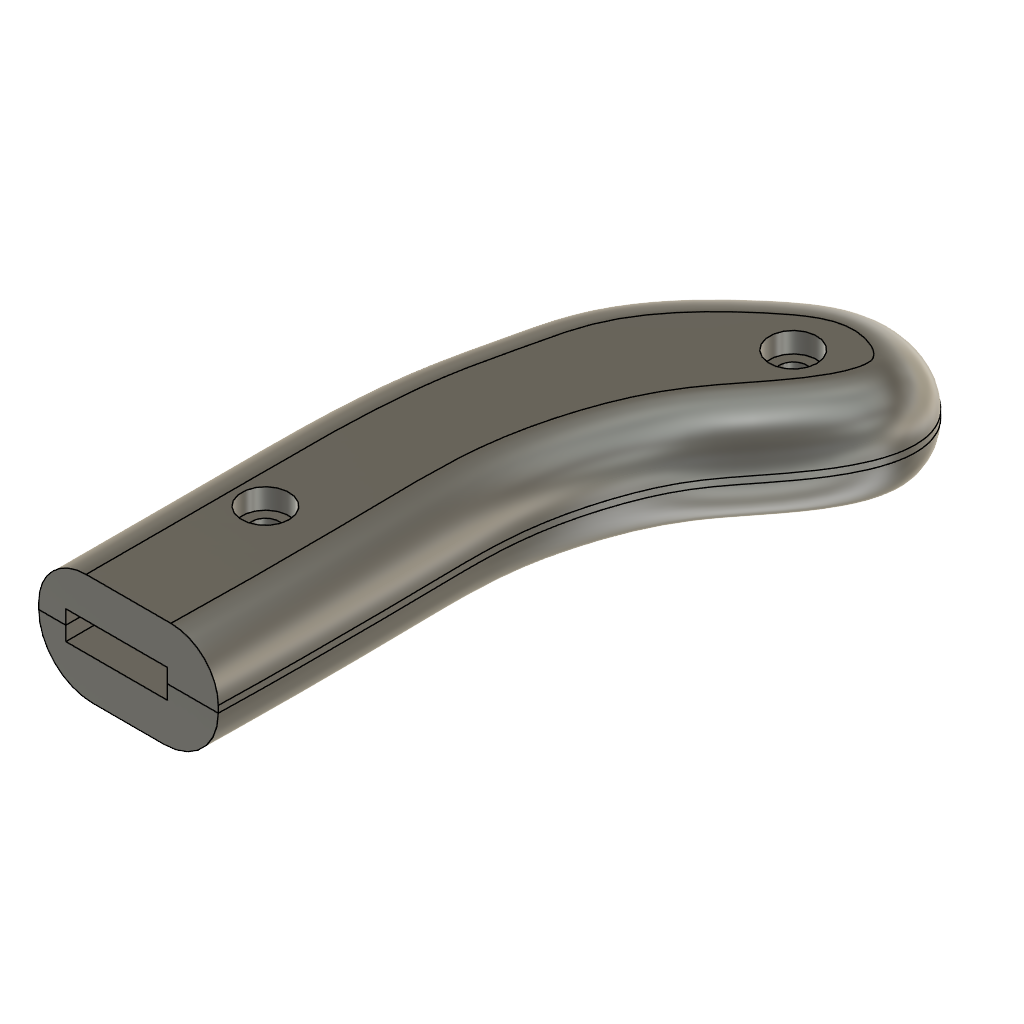
rack_handle (Autodesk Fusion 360 design; units mm, degrees)
part number: 2026-10-31-14-08-03-818
Autodesk Fusion 360 part; units mm, degrees
sketch "Sketch1" plane through (0, 0, 0) normal (0, 0, 1) x (1, 0, 0)
  line L0 (-7.5, 0) -> (7.5, 0)
  line L1 (7.5, 0) -> (7.5, 37)
  line L2 (7.5, 37) -> (-7.5, 37)
  line L3 (-7.5, 37) -> (-7.5, 0)
  arc A0 (7.5, 33) -> (3.5, 37) centre (3.5, 33) ccw
  arc A1 (-3.5, 37) -> (-7.5, 33) centre (-3.5, 33) ccw
  spline S0 degree 5 poles (-11.5, 0) (-11.5, 0.1964) (-11.4998, 0.8627) (-11.499, 2.6836) (-11.4971, 6.5461) (-11.4944, 12.661) (-11.4926, 18.7411) (-11.4942, 23.7765) (-11.4983, 27.24) (-11.5109, 30.0986) (-11.5138, 33.526) (-11.4572, 37.6506) (-11.2874, 42.3069) (-10.9623, 47.0376) (-10.4697, 51.3973) (-9.8513, 55.1652) (-9.1822, 58.3544) (-8.5348, 61.1068) (-7.9502, 63.632) (-7.4003, 66.121) (-6.7728, 68.6921) (-5.9239, 71.406) (-4.715, 74.2706) (-3.0647, 77.2483) (-0.9577, 80.2674) (1.556, 83.2437) (4.3816, 86.0885) (7.3422, 88.7451) (10.2864, 91.1577) (13.3024, 93.1642) (16.5166, 94.5809) (20.0236, 95.2277) (23.7599, 94.9782) (27.406, 93.7983) (30.5155, 91.7368) (32.6499, 88.9157) (33.4969, 85.5191) (33.0312, 81.7882) (31.5054, 77.9906) (29.3161, 74.3724) (26.9013, 71.1115) (24.6364, 68.2779) (22.7031, 65.7728) (21.0938, 63.3607) (19.715, 60.776) (18.4534, 57.7934) (17.2759, 54.3441) (16.25, 50.5096) (15.4785, 46.4111) (15.0382, 42.0502) (14.9508, 37.3279) (15.0617, 31.616) (15.1718, 24.5363) (15.219, 16.6784) (15.1847, 9.0086) (15.1016, 2.7613) (15.0348, -0.1466) (15.0063, -0.7371) (15, -0.3721) (15, 0) knots 0 0 0 0 0 0 0.018182 0.036364 0.054545 0.072727 0.090909 0.109091 0.127273 0.145455 0.163636 0.181818 0.2 0.218182 0.236364 0.254545 0.272727 0.290909 0.309091 0.327273 0.345455 0.363636 0.381818 0.4 0.418182 0.436364 0.454545 0.472727 0.490909 0.509091 0.527273 0.545455 0.563636 0.581818 0.6 0.618182 0.636364 0.654545 0.672727 0.690909 0.709091 0.727273 0.745455 0.763636 0.781818 0.8 0.818182 0.836364 0.854545 0.872727 0.890909 0.909091 0.927273 0.945455 0.963636 0.981818 1 1 1 1 1 1
  line L4 (15, -1.4596) -> (15, 1.4596)
  line L5 (15, 46.1457) -> (15, 27.8543)
  circle A2 centre (0, 22) radius 2.05
  line L6 (0, 22) -> (-7.5, 22) construction
  line L7 (0, 22) -> (7.5, 22) construction
  line L8 (-11.5, -1.8049) -> (-11.5, 1.8049)
  line L9 (-11.4851, 20.6483) -> (-11.5149, 33.3517)
  circle A3 centre (7.0828, 72.0757) radius 2
  circle A4 centre (7.0828, 72.0757) radius 2.1
  circle A5 centre (-0.8976, 46.6054) radius 2
  circle A6 centre (-0.8976, 46.6054) radius 2.1
  circle A7 centre (8.6082, 58.1337) radius 2
  circle A8 centre (8.6082, 58.1337) radius 2.1
  line L10 (0, 1.75) -> (0, 22.5)
  line L11 (1.75, 0) -> (22.5, 0)
  line L12 (-1.5998, 80.4412) -> (11.5998, 92.7436)
  line L13 (15, 0) -> (-11.5, 0)
  circle A9 centre (19, 81) radius 2.05
  point P0 (-11.5, 27)
  point P1 (-10.8099, 48.1063)
  point P2 (-8.1091, 62.9606)
  point P3 (-5.4083, 72.5258)
  point P4 (5, 86.5924)
  point P5 (20, 95)
  point P6 (26, 70)
  point P7 (19, 59)
  point P8 (15, 37)
  point P9 (32.8527, 87.3801)
  dimension "d11" = 15
  dimension "d13" = 4
  dimension "d14" = 4
  dimension "d15" = 4
  dimension "d16" = 4
  dimension "d17" = 7.5
  dimension "d18" = 7.5
  dimension "d19" = 7.5
  dimension "d20" = 7.5
  dimension "d22" = 4
  dimension "d23" = 4
  dimension "d35" = 4.1
  dimension "d36" = 15
  dimension "d54" = 4
  dimension "d55" = 4.2
  dimension "d56" = 4
  dimension "d57" = 4.2
  dimension "d58" = 4
  dimension "d59" = 4.2
  dimension "d69" = 22
  dimension "d70" = 4.1
  constraint horizontal L0
  constraint vertical L1
  constraint horizontal L2
  constraint vertical L3
  constraint coincident L1 A0.start
  constraint coincident L2 A0.end
  constraint coincident L3 A1.end
  constraint coincident L2 A1.start
  constraint tangent L2 A0
  constraint tangent L2 A1
  constraint midpoint S0.end L4
  constraint midpoint P8 L5
  constraint coincident L2 P8
  constraint coincident L0 S0.end
  constraint coincident A2.centre L6.start
  constraint coincident L3 L6.end
  constraint perpendicular L3 L6
  constraint coincident L1 L7.end
  constraint perpendicular L1 L7
  constraint equal L6 L7
  constraint midpoint S0.start L8
  constraint midpoint P0 L9
  constraint concentric A3 A4
  constraint concentric A5 A6
  constraint concentric A7 A8
  constraint coincident A2.centre L10
  constraint collinear L0 L11
  constraint parallel L8 L10
  constraint midpoint P4 L12
  constraint perpendicular L8 L13
  measures "d11" distance of L0.start L0.end
  measures "d13" distance of L2 A0.centre
  measures "d14" distance of L1 A0.centre
  measures "d15" distance of L3 A1.centre
  measures "d16" distance of L2 A1.centre
  measures "d17" distance of L0.end S0.end
  measures "d18" distance of L1.end P8
  measures "d19" distance of L1 L4.start
  measures "d20" distance of L1 L5.end
  measures "d22" distance of L3 S0.start
  measures "d23" distance of L3 P0
  measures "d35" diameter of A2
  measures "d36" distance of L2 A2.centre
  measures "d54" diameter of A3
  measures "d55" diameter of A4
  measures "d56" diameter of A5
  measures "d57" diameter of A6
  measures "d58" diameter of A7
  measures "d59" diameter of A8
  measures "d69" distance of origin A2.centre
  measures "d70" diameter of A9
extrude "Extrude1" add sketch "Sketch1" along normal blind 8 and the other way blind 8 contours L0 L1 L2 L3 A0 A1 L11 L13 | L1 L2 L3 S0 L8 L11 L13 | L2 L3 A1 | L1 L2 A0 | A3 | A4 | A5 | A6 | A7 | A8 makes body 1
extrude "Extrude2" cut sketch "Sketch1" along normal blind 2.1 and the other way blind 2.1 contours L0 L1 L2 L3 A0 A1 L11 L13 | A2 bodies 1
sketch "Sketch2" plane through (0, 0, -8) normal (0, 0, -1) x (1, 0, 0)
  circle A0 centre (0, -22) radius 2.7
  spline S0 degree 5 poles (-11.5, 0) (-11.5, -0.1964) (-11.4998, -0.8627) (-11.499, -2.6836) (-11.4971, -6.5461) (-11.4944, -12.661) (-11.4926, -18.7411) (-11.4942, -23.7765) (-11.4983, -27.24) (-11.5109, -30.0986) (-11.5138, -33.526) (-11.4572, -37.6506) (-11.2874, -42.3069) (-10.9623, -47.0376) (-10.4697, -51.3973) (-9.8513, -55.1652) (-9.1822, -58.3544) (-8.5348, -61.1068) (-7.9502, -63.632) (-7.4003, -66.121) (-6.7728, -68.6921) (-5.9239, -71.406) (-4.715, -74.2706) (-3.0647, -77.2483) (-0.9577, -80.2674) (1.556, -83.2437) (4.3816, -86.0885) (7.3422, -88.7451) (10.2864, -91.1577) (13.3024, -93.1642) (16.5166, -94.5809) (20.0236, -95.2277) (23.7599, -94.9782) (27.406, -93.7983) (30.5155, -91.7368) (32.6499, -88.9157) (33.4969, -85.5191) (33.0312, -81.7882) (31.5054, -77.9906) (29.3161, -74.3724) (26.9013, -71.1115) (24.6364, -68.2779) (22.7031, -65.7728) (21.0938, -63.3607) (19.715, -60.776) (18.4534, -57.7934) (17.2759, -54.3441) (16.25, -50.5096) (15.4785, -46.4111) (15.0382, -42.0502) (14.9508, -37.3279) (15.0617, -31.616) (15.1718, -24.5363) (15.219, -16.6784) (15.1847, -9.0086) (15.1181, -4.0069) (15.0681, -1.4327) (15.0411, -0.3633) (15.0298, -0.0011) (15.0297, 0) knots 0 0 0 0 0 0 0.018182 0.036364 0.054545 0.072727 0.090909 0.109091 0.127273 0.145455 0.163636 0.181818 0.2 0.218182 0.236364 0.254545 0.272727 0.290909 0.309091 0.327273 0.345455 0.363636 0.381818 0.4 0.418182 0.436364 0.454545 0.472727 0.490909 0.509091 0.527273 0.545455 0.563636 0.581818 0.6 0.618182 0.636364 0.654545 0.672727 0.690909 0.709091 0.727273 0.745455 0.763636 0.781818 0.8 0.818182 0.836364 0.854545 0.872727 0.890909 0.909091 0.927273 0.945455 0.963636 0.981818 0.981874 0.981874 0.981874 0.981874 0.981874 0.981874
  circle A1 centre (0, -22) radius 2.05
  line L0 (15.0297, 0) -> (-11.5, 0)
  circle A2 centre (19, -81) radius 2.05
  circle A3 centre (19, -81) radius 2.7
  dimension "d41" = 5.4
  dimension "d71" = 5.4
  constraint concentric A2 A3
  measures "d41" diameter of A0
  measures "d71" diameter of A3
extrude "Extrude4" cut sketch "Sketch2" against normal blind 4 contours A0 | A1 | A3 bodies 1
sketch "Sketch3" plane through (0, 0, 8) normal (0, 0, 1) x (-1, 0, 0)
  circle A0 centre (0, -22) radius 2.05
  circle A1 centre (-19, -81) radius 2.05
  line L0 (11.5, 0) -> (-15.0297, 0)
  spline S0 degree 5 poles (-15.0297, 0) (-15.0298, -0.0011) (-15.0411, -0.3633) (-15.0681, -1.4327) (-15.1181, -4.0069) (-15.1847, -9.0086) (-15.219, -16.6784) (-15.1718, -24.5363) (-15.0617, -31.616) (-14.9508, -37.3279) (-15.0382, -42.0502) (-15.4785, -46.4111) (-16.25, -50.5096) (-17.2759, -54.3441) (-18.4534, -57.7934) (-19.715, -60.776) (-21.0938, -63.3607) (-22.7031, -65.7728) (-24.6364, -68.2779) (-26.9013, -71.1115) (-29.3161, -74.3724) (-31.5054, -77.9906) (-33.0312, -81.7882) (-33.4969, -85.5191) (-32.6499, -88.9157) (-30.5155, -91.7368) (-27.406, -93.7983) (-23.7599, -94.9782) (-20.0236, -95.2277) (-16.5166, -94.5809) (-13.3024, -93.1642) (-10.2864, -91.1577) (-7.3422, -88.7451) (-4.3816, -86.0885) (-1.556, -83.2437) (0.9577, -80.2674) (3.0647, -77.2483) (4.715, -74.2706) (5.9239, -71.406) (6.7728, -68.6921) (7.4003, -66.121) (7.9502, -63.632) (8.5348, -61.1068) (9.1822, -58.3544) (9.8513, -55.1652) (10.4697, -51.3973) (10.9623, -47.0376) (11.2874, -42.3069) (11.4572, -37.6506) (11.5138, -33.526) (11.5109, -30.0986) (11.4983, -27.24) (11.4942, -23.7765) (11.4926, -18.7411) (11.4944, -12.661) (11.4971, -6.5461) (11.499, -2.6836) (11.4998, -0.8627) (11.5, -0.1964) (11.5, 0) knots -0.981874 -0.981874 -0.981874 -0.981874 -0.981874 -0.981874 -0.981818 -0.963636 -0.945455 -0.927273 -0.909091 -0.890909 -0.872727 -0.854545 -0.836364 -0.818182 -0.8 -0.781818 -0.763636 -0.745455 -0.727273 -0.709091 -0.690909 -0.672727 -0.654545 -0.636364 -0.618182 -0.6 -0.581818 -0.563636 -0.545455 -0.527273 -0.509091 -0.490909 -0.472727 -0.454545 -0.436364 -0.418182 -0.4 -0.381818 -0.363636 -0.345455 -0.327273 -0.309091 -0.290909 -0.272727 -0.254545 -0.236364 -0.218182 -0.2 -0.181818 -0.163636 -0.145455 -0.127273 -0.109091 -0.090909 -0.072727 -0.054545 -0.036364 -0.018182 0 0 0 0 0 0
  circle A2 centre (-19, -81) radius 3.5
  circle A3 centre (0, -22) radius 3.5
  dimension "d72" = 7
  dimension "d73" = 7
  constraint concentric A1 A2
  constraint concentric A0 A3
  measures "d72" diameter of A2
  measures "d73" diameter of A3
extrude "Extrude9" cut sketch "Sketch3" against normal blind 3 contours A2 | A3 bodies 1
fillet "Fillet1" radius 7 1 edges at (13.3565, 93.0194, 8) on bodies 1
fillet "Fillet2" radius 8 1 edges at (13.3565, 93.0194, -8) on bodies 1
split "Split1" by plane through (0, 0, 0) normal (0, 0, 1) bodies 1 makes body 2 at (-0.0268, 38.543, 8)
extrude "Extrude5" add sketch "Sketch1" along normal blind 3 contours A3 | A5 bodies 1
extrude "Extrude6" add sketch "Sketch1" against normal blind 3 contours A7 bodies 2
extrude "Extrude7" cut sketch "Sketch1" along normal blind 3.2 contours A3 | A4 | A5 | A6 bodies 2
extrude "Extrude8" cut sketch "Sketch1" against normal blind 3.2 contours A7 | A8 bodies 1
equation "sleeve_depth = 27 mm"
equation "sleeve_width = 15 mm"
equation "sleeve_thickness = 4.2 mm"
equation "d11 = sleeve_width"
equation "handle_thickness_front = 8 mm"
equation "handle_thickness_rear = 8 mm"
equation "d26 = handle_thickness_front"
equation "d28 = handle_thickness_rear"
equation "d30 = sleeve_thickness / 2"
equation "d32 = sleeve_thickness / 2"
equation "bolt_hole_diameter = 4.1 mm"
equation "d35 = bolt_hole_diameter"
equation "d41 = heat_set_insert_diameter"
equation "heat_set_insert_diameter = 5.4 mm"
equation "heat_set_insert_depth = 4 mm"
equation "d44 = -heat_set_insert_depth"
equation "d49 = handle_thickness_rear"
equation "peg_diameter = 4 mm"
equation "peg_hole_diameter = peg_diameter + 0.2 mm"
equation "peg_depth = 3 mm"
equation "peg_hole_depth = peg_depth + 0.2 mm"
equation "d54 = peg_diameter"
equation "d55 = peg_hole_diameter"
equation "d56 = peg_diameter"
equation "d57 = peg_hole_diameter"
equation "d58 = peg_diameter"
equation "d59 = peg_hole_diameter"
equation "d60 = peg_depth"
equation "d62 = -peg_depth"
equation "d64 = peg_hole_depth"
equation "d66 = -peg_hole_depth"
